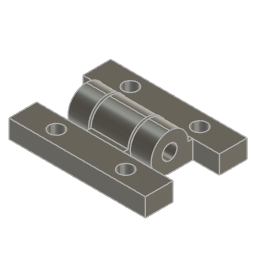
Hinge M3 (Autodesk Fusion 360 design; units mm, degrees)
part number: 2026-04-11-15-28-25-390
Autodesk Fusion 360 part; units mm, degrees
sketch "Sketch1" plane through (0, 0, 0) normal (0, 0, 1) x (1, 0, 0)
  line L0 (14.75, 0.5) -> (-14.75, 0.5)
  line L1 (-14.75, 0.5) -> (-14.75, -5.5)
  line L2 (-14.75, -5.5) -> (14.75, -5.5)
  line L3 (14.75, -5.5) -> (14.75, 0.5)
  line L4 (-4, 0.5) -> (4, 0.5)
  line L5 (4, 0.5) -> (4, 9.5)
  line L6 (4, 9.5) -> (-4, 9.5)
  line L7 (-4, 9.5) -> (-4, 0.5)
  line L8 (4.5, 1.5) -> (9, 1.5)
  line L9 (9, 1.5) -> (9, 10.5)
  line L10 (9, 10.5) -> (4.5, 10.5)
  line L11 (4.5, 10.5) -> (4.5, 1.5)
  line L12 (-4.5, 1.5) -> (-9, 1.5)
  line L13 (-9, 1.5) -> (-9, 10.5)
  line L14 (-9, 10.5) -> (-4.5, 10.5)
  line L15 (-4.5, 10.5) -> (-4.5, 1.5)
  line L16 (14.75, 10.5) -> (-14.75, 10.5)
  line L17 (-14.75, 10.5) -> (-14.75, 16.5)
  line L18 (-14.75, 16.5) -> (14.75, 16.5)
  line L19 (14.75, 16.5) -> (14.75, 10.5)
  circle A0 centre (7.5, -2.5) radius 1.575
  circle A1 centre (-7.5, -2.5) radius 1.575
  circle A2 centre (7.5, 13.5) radius 1.575
  circle A3 centre (-7.5, 13.5) radius 1.575
  dimension "d32" = 3.15
  dimension "d33" = 3.15
  dimension "d34" = 3.15
  dimension "d35" = 3.15
  constraint horizontal L0
  constraint perpendicular L0 L1
  constraint parallel L0 L2
  constraint parallel L1 L3
  constraint horizontal L4
  constraint vertical L5
  constraint horizontal L6
  constraint vertical L7
  constraint coincident L0 L4.start
  constraint horizontal L8
  constraint vertical L9
  constraint horizontal L10
  constraint vertical L11
  constraint horizontal L12
  constraint vertical L13
  constraint horizontal L14
  constraint vertical L15
  constraint horizontal L16
  constraint vertical L17
  constraint horizontal L18
  constraint vertical L19
  measures "d32" diameter of A2
  measures "d33" diameter of A3
  measures "d34" diameter of A0
  measures "d35" diameter of A1
extrude "Extrude1" add sketch "Sketch1" along normal blind 4 contours L0 L1 L2 L3 L4 | L10 L14 L16 L17 L18 L19 makes body 1 at (-12.8583, 13.5, 0) makes body 2 at (-12.8583, -2.5, 0)
extrude "Extrude2" add sketch "Sketch1" along normal blind 8 separate body contours L0 L4 L5 L6 L7 | L8 L9 L10 L11 L16 | L12 L13 L14 L15 L16 makes body 3 at (4.5, 7.5, 5.3333) makes body 4 at (-4, 6.5, 5.3333) makes body 5 at (-4.5, 7.5, 5.3333)
sketch "Sketch5" plane through (-9, 0, 0) normal (-1, 0, 0) x (0, -1, 0)
  line L0 (-10.5, 0) -> (-1.5, 0)
  line L1 (-1.5, 0) -> (-1.5, 8)
  line L2 (-1.5, 8) -> (-10.5, 8)
  line L3 (-10.5, 8) -> (-10.5, 0)
  point P0 (-5.5, 4)
sketch "Sketch6" plane through (9, 0, 0) normal (1, 0, 0) x (0, 1, 0)
  line L0 (1.5, 0) -> (10.5, 0)
  line L1 (10.5, 0) -> (10.5, 8)
  line L2 (10.5, 8) -> (1.5, 8)
  line L3 (1.5, 8) -> (1.5, 0)
  point P0 (5.5, 4)
hole "Hole3" at (9, 5.5, 4) direction (-1, 0, 0) diameter 3.2 depth 13 tip angle 180 bodies 3 4
hole "Hole4" at (-9, 5.5, 4) direction (1, 0, 0) diameter 2.85 depth 4.5 tip angle 180 bodies 5
sketch "Sketch7" plane through (0, 0, 8) normal (0, 0, 1) x (-1, 0, 0)
  line L0 (-9, -1.5) -> (-9, -10.5)
  line L1 (-9, -10.5) -> (-4.5, -10.5)
  line L2 (-4.5, -10.5) -> (-4.5, -1.5)
  line L3 (-4.5, -1.5) -> (-9, -1.5)
  line L4 (-9, -10.5) -> (-4.5, -10.5)
  line L5 (-4.5, -10.5) -> (-4.5, -9.5)
  line L6 (-4.5, -9.5) -> (-9, -9.5)
  line L7 (-9, -9.5) -> (-9, -10.5)
  line L8 (4.5, -10.5) -> (9, -10.5)
  line L9 (9, -10.5) -> (9, -9.5)
  line L10 (9, -9.5) -> (4.5, -9.5)
  line L11 (4.5, -9.5) -> (4.5, -10.5)
  line L12 (4, -0.5) -> (-4, -0.5)
  line L13 (-4, -0.5) -> (-4, -1.5)
  line L14 (-4, -1.5) -> (4, -1.5)
  line L15 (4, -1.5) -> (4, -0.5)
  constraint horizontal L4
  constraint vertical L5
  constraint horizontal L6
  constraint vertical L7
  constraint coincident L2 L5.end
  constraint coincident L0.end L1.start
  constraint horizontal L8
  constraint vertical L9
  constraint horizontal L10
  constraint vertical L11
  constraint horizontal L12
  constraint vertical L13
  constraint horizontal L14
  constraint vertical L15
extrude "Extrude5" cut sketch "Sketch7" against normal blind 4 contours L0 L1 L2 L4 L5 L6 L7 | L8 L9 L10 L11 | L12 L13 L14 L15 bodies 5 3 4
fillet "Fillet2" radius 4 9 edges at (6.75, 9.5, 8) (6.75, 1.5, 8) (6.75, 1.5, 0) (0, 9.5, 8) (0, 1.5, 8) (0, 9.5, 0) (-6.75, 1.5, 8) (-6.75, 9.5, 8) (-6.75, 1.5, 0) on bodies 3 4 5
